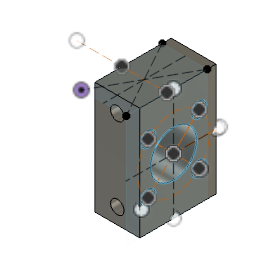
Cross slide block (Autodesk Fusion 360 design; units mm, degrees)
Autodesk Fusion 360 part; units mm, degrees
sketch "Sketch1" plane through (0, 0, 0) normal (0, 1, 0) x (1, 0, 0)
  line L0 (0, -20) -> (10, -20)
  line L1 (10, -20) -> (10, 5)
  line L2 (10, 5) -> (0, 5)
  line L3 (0, 5) -> (0, -20)
  dimension "d1" = 10
  dimension "d2" = 25
  constraint horizontal L0
  constraint vertical L1
  constraint horizontal L2
  constraint vertical L3
  measures "d1" distance of L0.start L0.end
  measures "d2" distance of L0.start L2.end
extrude "Extrude1" add sketch "Sketch1" along normal blind 18
sketch "Sketch2" plane through (0, 0, 20) normal (0, 0, 1) x (-1, 0, 0)
  line L0 (0, 0) -> (-10, 0)
  line L1 (-10, 0) -> (-10, -18)
  line L2 (-10, -18) -> (0, -18)
  line L3 (0, -18) -> (0, 0)
  line L4 (0, -18) -> (-10, 0) construction
  line L5 (-10, -18) -> (0, 0) construction
  line L6 (10, -9) -> (-10, -9) construction
  line L7 (-5, -18) -> (-5, 0) construction
  point P0 (0, -9)
  constraint coincident L2.end L3.start
  constraint coincident L0.end L1.start
  constraint coincident L1.end L2.start
  constraint coincident L0.start L3.end
  constraint midpoint L6 P0
  constraint coincident L3 P0
  constraint coincident L1 L6.end
  constraint perpendicular L1 L6
  constraint midpoint L2 L7.start
  constraint midpoint L0 L7.end
sketch "Sketch3" plane through (0, 18, 0) normal (0, 1, 0) x (-1, 0, 0)
  line L0 (0, -5) -> (0, 20)
  line L1 (0, 20) -> (-10, 20)
  line L2 (-10, 20) -> (-10, -5)
  line L3 (-10, -5) -> (0, -5)
  line L4 (0, -5) -> (-10, 20) construction
  line L5 (-10, -5) -> (0, 20) construction
  line L6 (-5, -5) -> (-5, 20) construction
  line L7 (0, 7.5) -> (-10, 7.5) construction
  line L8 (0, 16.5) -> (-10, 16.5) construction
  line L9 (0, -1.5) -> (-10, -1.5) construction
  circle A0 centre (-5, -1.5) radius 1.5
  circle A1 centre (-5, 16.5) radius 1.5
  circle A2 centre (-5, -1.5) radius 3
  circle A3 centre (-5, 16.5) radius 3
  dimension "d5" = 9
  dimension "d6" = -9
  dimension "d7" = 3
  dimension "d8" = 3
  dimension "d11" = 6
  dimension "d12" = 6
  constraint coincident L0.start L3.end
  constraint coincident L1.end L2.start
  constraint coincident L2.end L3.start
  constraint coincident L0.end L1.start
  constraint midpoint L3 L6.start
  constraint midpoint L1 L6.end
  constraint midpoint L0 L7.start
  constraint midpoint L2 L7.end
  constraint midpoint L9 A0.centre
  constraint midpoint L8 A1.centre
  constraint concentric A0 A2
  constraint concentric A1 A3
  measures "d7" diameter of A0
  measures "d8" diameter of A1
  measures "d11" diameter of A2
  measures "d12" diameter of A3
extrude "Extrude2" cut sketch "Sketch3" against normal blind 100 contours A0 | A1
extrude "Extrude3" cut sketch "Sketch3" against normal blind 5 contours A2 | A3
sketch "Sketch4" plane through (10, 0, 0) normal (1, 0, 0) x (0, 1, 0)
  line L0 (0, 20) -> (0, -5)
  line L1 (0, -5) -> (18, -5)
  line L2 (18, -5) -> (18, 20)
  line L3 (18, 20) -> (0, 20)
  line L4 (18, 7.5) -> (0, 7.5) construction
  line L5 (10.5, 20) -> (10.5, -5) construction
  circle A0 centre (10.5, 7.5) radius 5.1
  circle A1 centre (10.5, 7.5) radius 8 construction
  line L6 (10.5, 7.5) -> (17.2932, 14.2932) construction
  line L7 (10.5, 7.5) -> (20.1071, 7.5) construction
  line L8 (10.5, 7.5) -> (3.2488, 14.7512) construction
  line L9 (10.5, 7.5) -> (20.7548, 7.5) construction
  line L10 (3.2488, 14.7512) -> (16.5168, 1.4832) construction
  line L11 (17.2932, 14.2932) -> (3.3397, 0.3397) construction
  circle A2 centre (4.8431, 13.1569) radius 1.6
  circle A3 centre (16.1569, 13.1569) radius 1.6
  circle A4 centre (16.1569, 1.8431) radius 1.6
  circle A5 centre (4.8431, 1.8431) radius 1.6
  dimension "d15" = -10.5
  dimension "d16" = 10.2
  dimension "d19" = 16
  dimension "d20" = 45
  dimension "d21" = 135
  dimension "d22" = 3.2
  dimension "d23" = 3.2
  dimension "d25" = 3.2
  dimension "d26" = 3.2
  constraint midpoint L2 L4.start
  constraint midpoint L0 L4.end
  constraint midpoint L5 A0.centre
  constraint concentric A0 A1
  constraint horizontal L7
  constraint coincident A0.centre A1.centre
  constraint horizontal L9
  constraint parallel L8 L10
  constraint parallel L6 L11
  constraint coincident A1 A2.centre
  constraint coincident L10 A2.centre
  constraint coincident A1 A3.centre
  constraint coincident L6 A3.centre
  constraint coincident A1 A4.centre
  constraint coincident L10 A4.centre
  constraint coincident A1 A5.centre
  constraint coincident L11 A5.centre
  measures "d16" diameter of A0
  measures "d19" diameter of A1
  measures "d20" angle of L6 L7
  measures "d21" angle of L8 L9
  measures "d22" diameter of A2
  measures "d23" diameter of A3
  measures "d25" diameter of A4
  measures "d26" diameter of A5
extrude "Extrude4" cut sketch "Sketch4" against normal blind 25 contours A0
extrude "Extrude5" cut sketch "Sketch4" against normal blind 30 contours A2 | A3 | A4 | A5
extrude "Extrude6" cut sketch "Sketch3" against normal blind 8 contours A2 | A3
extrude "Extrude7" add sketch "Sketch3" along normal blind 2 contours L0 L1 L2 L3
extrude "Extrude8" cut 1 faces at (8.7465, 0, 10.2183) along direction (0, 1, 0) blind 2
extrude "Extrude9" cut 1 faces at (8.7465, 2, 10.2183) along direction (0, 1, 0) blind 1
equation "d20 = 45 °"
equation "d21 = 135 °"
